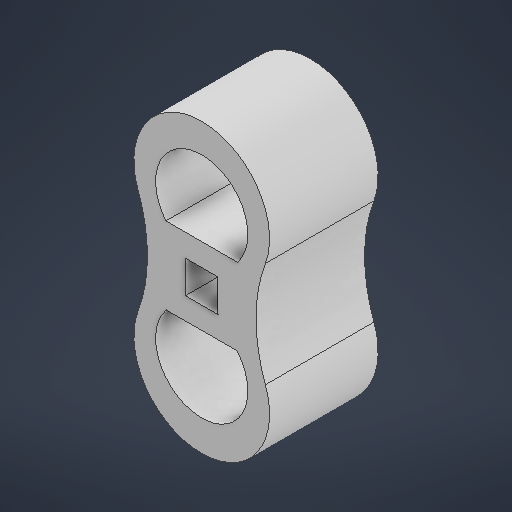
# Autodesk Inventor part: lobulo
Saved by Autodesk Inventor 2027 (Build 310192060, 192F)
## iProperties
Created: 2026-10-23
Part Number: lobulo
Material: Genérico
Document SubType Name: Modeling
Designer: Giovanna Oliveira
Density: 1 g/cm^3
Appearance: Padrão
Author: Giovanna Oliveira
Autodesk Inventor part; units mm, degrees
ref_plane "YZ Plane" through (0, 0, 0) normal (1, 0, 0) x (0, 1, 0)
ref_plane "XZ Plane" through (0, 0, 0) normal (0, 1, 0) x (-1, 0, 0)
ref_plane "XY Plane" through (0, 0, 0) normal (0, 0, 1) x (1, 0, 0)
sketch "Esboço1" plane through (0, 0, 0) normal (0, 0, 1) x (1, 0, 0)
  arc A0 (-28.6109, 137.2433) -> (-75.5293, 137.2433) centre (-52.0701, 145.8841) ccw
  arc A1 (-75.5293, 98.5482) -> (-28.6109, 98.5482) centre (-52.0701, 89.9073) ccw
  arc A2 (-28.6109, 137.2433) -> (-28.6109, 98.5482) centre (23.916, 117.8957) ccw
  arc A3 (-75.5293, 98.5482) -> (-75.5293, 137.2433) centre (-128.0562, 117.8957) ccw
  constraints: 8 point on circle, 4 centre point, 4 tangent
extrude "Extrusão1" add sketch "Esboço1" along normal blind 40
sketch "Esboço2" plane through (0, 0, 40) normal (0, 0, 1) x (1, 0, 0)
  arc A0 (-28.6109, 137.2433) -> (-75.5293, 137.2433) centre (-52.0701, 145.8841) ccw construction
  line L0 (-46.0701, 124.214) -> (-58.0701, 124.214)
  line L1 (-58.0701, 124.214) -> (-58.0701, 112.214)
  line L2 (-58.0701, 112.214) -> (-46.0701, 112.214)
  line L3 (-46.0701, 112.214) -> (-46.0701, 124.214)
  line L4 (-46.0701, 124.214) -> (-58.0701, 112.214) construction
  line L5 (-58.0701, 124.214) -> (-46.0701, 112.214) construction
  arc A1 (-38.8769, 132.493) -> (-65.2633, 132.493) centre (-52.0701, 143.214) ccw
  arc A2 (-65.0953, 104.1385) -> (-39.0954, 104.1984) centre (-52.0701, 93.214) ccw
  line L6 (-38.8769, 132.493) -> (-65.2633, 132.493)
  line L7 (-30.959, 132.493) -> (-12.4906, 132.493) construction
  line L8 (-39.0954, 104.1984) -> (-65.0953, 104.1385)
  point P0 (0, 0)
  point P1 (-52.0701, 118.214)
  constraints: 18 end point, 5 point on circle, 3 horizontal, 2 centre point, 2 midpoint, 2 parallel, 1 perpendicular
extrude "Extrusão2" cut sketch "Esboço2" against normal blind 40
